Autodesk Fusion 360 part; units mm, degrees
(part 2 of 2)
extrude "PSU bottom support rail'" add sketch "草图1 (14)" along normal blind 6 separate body makes body 14 in component "04_PSU_Shelf_front"
ref_plane "工作平面2" through (0, 0, 14) normal (0, 0, 1) x (1, 0, 0) in component "04_PSU_Shelf_front"
sketch "草图2 (14)" plane through (0, 0, 14) normal (0, 0, 1) x (1, 0, 0) in component "04_PSU_Shelf_front"
  circle A0 centre (-13, 121) radius 1.7
extrude "M3x10 shelf to frame (1)" cut sketch "草图2 (14)" along normal blind 6 bodies 1 in component "01_Side_L_rear"
extrude "拉伸2'" cut sketch "草图2 (14)" along normal blind 6 bodies 14 in component "04_PSU_Shelf_front"
ref_plane "工作平面3" through (0, 0, 14) normal (0, 0, 1) x (1, 0, 0) in component "04_PSU_Shelf_front"
sketch "草图3 (14)" plane through (0, 0, 14) normal (0, 0, 1) x (1, 0, 0) in component "04_PSU_Shelf_front"
  circle A0 centre (257, 121) radius 1.7
extrude "M3x10 shelf to frame (1)'" cut sketch "草图3 (14)" along normal blind 6 bodies 3 in component "01_Side_R_rear"
extrude "拉伸3'" cut sketch "草图3 (14)" along normal blind 6 bodies 14 in component "04_PSU_Shelf_front"
ref_plane "工作平面4" through (0, 0, 14) normal (0, 0, 1) x (1, 0, 0) in component "04_PSU_Shelf_front"
sketch "草图4 (13)" plane through (0, 0, 14) normal (0, 0, 1) x (1, 0, 0) in component "04_PSU_Shelf_front"
  circle A0 centre (14, 117) radius 1.7
extrude "Hoop position adjustment end 1'" cut sketch "草图4 (13)" along normal blind 6 bodies 14 in component "04_PSU_Shelf_front"
ref_plane "工作平面5" through (0, 0, 14) normal (0, 0, 1) x (1, 0, 0) in component "04_PSU_Shelf_front"
sketch "草图5 (13)" plane through (0, 0, 14) normal (0, 0, 1) x (1, 0, 0) in component "04_PSU_Shelf_front"
  circle A0 centre (14, 125) radius 1.7
extrude "Hoop position adjustment end 2'" cut sketch "草图5 (13)" along normal blind 6 bodies 14 in component "04_PSU_Shelf_front"
ref_plane "工作平面6" through (0, 0, 14) normal (0, 0, 1) x (1, 0, 0) in component "04_PSU_Shelf_front"
sketch "草图6 (9)" plane through (0, 0, 14) normal (0, 0, 1) x (1, 0, 0) in component "04_PSU_Shelf_front"
  line L0 (12.3, 117) -> (15.7, 117)
  line L1 (15.7, 117) -> (15.7, 125)
  line L2 (15.7, 125) -> (12.3, 125)
  line L3 (12.3, 125) -> (12.3, 117)
extrude "Hoop position adjustment bridge'" cut sketch "草图6 (9)" along normal blind 6 bodies 14 in component "04_PSU_Shelf_front"
ref_plane "工作平面7" through (0, 0, 14) normal (0, 0, 1) x (1, 0, 0) in component "04_PSU_Shelf_front"
sketch "草图7 (9)" plane through (0, 0, 14) normal (0, 0, 1) x (1, 0, 0) in component "04_PSU_Shelf_front"
  circle A0 centre (166, 117) radius 1.7
extrude "Hoop position adjustment end 1 (1)'" cut sketch "草图7 (9)" along normal blind 6 bodies 14 in component "04_PSU_Shelf_front"
ref_plane "工作平面8" through (0, 0, 14) normal (0, 0, 1) x (1, 0, 0) in component "04_PSU_Shelf_front"
sketch "草图8 (9)" plane through (0, 0, 14) normal (0, 0, 1) x (1, 0, 0) in component "04_PSU_Shelf_front"
  circle A0 centre (166, 125) radius 1.7
extrude "Hoop position adjustment end 2 (1)'" cut sketch "草图8 (9)" along normal blind 6 bodies 14 in component "04_PSU_Shelf_front"
ref_plane "工作平面9" through (0, 0, 14) normal (0, 0, 1) x (1, 0, 0) in component "04_PSU_Shelf_front"
sketch "草图9 (9)" plane through (0, 0, 14) normal (0, 0, 1) x (1, 0, 0) in component "04_PSU_Shelf_front"
  line L0 (164.3, 117) -> (167.7, 117)
  line L1 (167.7, 117) -> (167.7, 125)
  line L2 (167.7, 125) -> (164.3, 125)
  line L3 (164.3, 125) -> (164.3, 117)
extrude "Hoop position adjustment bridge (1)'" cut sketch "草图9 (9)" along normal blind 6 bodies 14 in component "04_PSU_Shelf_front"
ref_plane "工作平面10" through (0, 0, 20) normal (0, 0, 1) x (1, 0, 0) in component "04_PSU_Shelf_front"
sketch "草图10 (7)" plane through (0, 0, 20) normal (0, 0, 1) x (1, 0, 0) in component "04_PSU_Shelf_front"
  line L0 (17.5, 106) -> (19.5, 106)
  line L1 (19.5, 106) -> (19.5, 136)
  line L2 (19.5, 136) -> (17.5, 136)
  line L3 (17.5, 136) -> (17.5, 106)
extrude "PSU fore aft locating stop'" add sketch "草图10 (7)" along normal blind 6 bodies 14 in component "04_PSU_Shelf_front"
ref_plane "工作平面11" through (0, 0, 20) normal (0, 0, 1) x (1, 0, 0) in component "04_PSU_Shelf_front"
sketch "草图11 (5)" plane through (0, 0, 20) normal (0, 0, 1) x (1, 0, 0) in component "04_PSU_Shelf_front"
  line L0 (160.5, 106) -> (162.5, 106)
  line L1 (162.5, 106) -> (162.5, 136)
  line L2 (162.5, 136) -> (160.5, 136)
  line L3 (160.5, 136) -> (160.5, 106)
extrude "PSU fore aft locating stop (1)'" add sketch "草图11 (5)" along normal blind 6 bodies 14 in component "04_PSU_Shelf_front"
ref_plane "工作平面12" through (0, 0, 20) normal (0, 0, 1) x (1, 0, 0) in component "04_PSU_Shelf_front"
sketch "草图12 (5)" plane through (0, 0, 20) normal (0, 0, 1) x (1, 0, 0) in component "04_PSU_Shelf_front"
  line L0 (19.5, 131.5) -> (160.5, 131.5)
  line L1 (160.5, 131.5) -> (160.5, 133.5)
  line L2 (160.5, 133.5) -> (19.5, 133.5)
  line L3 (19.5, 133.5) -> (19.5, 131.5)
extrude "PSU fan-side lower-edge lip" add sketch "草图12 (5)" along normal blind 6 bodies 14 in component "04_PSU_Shelf_front"
ref_plane "工作平面1" through (0, -117, 0) normal (0, 1, 0) x (0, 0, 1) in component "05_PSU_Hoop_front"
sketch "草图1 (15)" plane through (0, -117, 0) normal (0, 1, 0) x (1, 0, 0) in component "05_PSU_Hoop_front"
  line L0 (10, -20, 234) -> (18, -20, 234)
  line L1 (18, -20, 234) -> (18, -171, 234)
  line L2 (18, -171, 234) -> (162, -171, 234)
  line L3 (162, -171, 234) -> (162, -20, 234)
  line L4 (162, -20, 234) -> (170, -20, 234)
  line L5 (170, -20, 234) -> (170, -179, 234)
  line L6 (170, -179, 234) -> (10, -179, 234)
  line L7 (10, -179, 234) -> (10, -20, 234)
extrude "Removable PSU retaining hoop'" add sketch "草图1 (15)" along normal blind 8 separate body contours L0 L1 L2 L3 L4 L5 L6 L7 in plane through (0, 117, 0) normal (0, 1, 0) makes body 15 in component "05_PSU_Hoop_front"
ref_plane "工作平面2" through (0, 0, 20) normal (0, 0, 1) x (1, 0, 0) in component "05_PSU_Hoop_front"
sketch "草图2 (15)" plane through (0, 0, 20) normal (0, 0, 1) x (1, 0, 0) in component "05_PSU_Hoop_front"
  circle A0 centre (14, 121) radius 2.35
extrude "M3 long insert from underside'" cut sketch "草图2 (15)" along normal blind 8.2 bodies 15 in component "05_PSU_Hoop_front"
ref_plane "工作平面3" through (0, 0, 20) normal (0, 0, 1) x (1, 0, 0) in component "05_PSU_Hoop_front"
sketch "草图3 (15)" plane through (0, 0, 20) normal (0, 0, 1) x (1, 0, 0) in component "05_PSU_Hoop_front"
  circle A0 centre (166, 121) radius 2.35
extrude "M3 long insert from underside (1)'" cut sketch "草图3 (15)" along normal blind 8.2 bodies 15 in component "05_PSU_Hoop_front"
ref_plane "工作平面1" through (0, 0, 198) normal (0, 0, 1) x (1, 0, 0) in component "06_GPU_RearTower"
sketch "草图1 (16)" plane through (0, 0, 198) normal (0, 0, 1) x (1, 0, 0) in component "06_GPU_RearTower"
  line L0 (-38, 130) -> (-5, 130)
  line L1 (-5, 130) -> (-5, 226)
  line L2 (-5, 226) -> (-38, 226)
  line L3 (-38, 226) -> (-38, 130)
extrude "GPU tower foot" add sketch "草图1 (16)" along normal blind 6 separate body makes body 16 in component "06_GPU_RearTower"
ref_plane "工作平面2" through (0, 0, 204) normal (0, 0, 1) x (1, 0, 0) in component "06_GPU_RearTower"
sketch "草图2 (16)" plane through (0, 0, 204) normal (0, 0, 1) x (1, 0, 0) in component "06_GPU_RearTower"
  line L0 (-38, 130) -> (-30, 130)
  line L1 (-30, 130) -> (-30, 226)
  line L2 (-30, 226) -> (-38, 226)
  line L3 (-38, 226) -> (-38, 130)
extrude "GPU rear frame" add sketch "草图2 (16)" along normal blind 146 bodies 16 in component "06_GPU_RearTower"
ref_plane "工作平面3" through (-38, 0, 0) normal (1, 0, 0) x (0, 1, 0) in component "06_GPU_RearTower"
sketch "草图3 (16)" plane through (-38, 0, 0) normal (1, 0, 0) x (0, 0, -1) in component "06_GPU_RearTower"
  line L0 (-214, 144) -> (-212, 146)
  line L1 (-212, 146) -> (-212, 210)
  line L2 (-212, 210) -> (-214, 212)
  line L3 (-214, 212) -> (-308, 212)
  line L4 (-308, 212) -> (-310, 210)
  line L5 (-310, 210) -> (-310, 146)
  line L6 (-310, 146) -> (-308, 144)
  line L7 (-308, 144) -> (-214, 144)
extrude "Open display connector access" cut sketch "草图3 (16)" along normal blind 8 bodies 16 in component "06_GPU_RearTower"
ref_plane "工作平面4" through (0, 0, 198) normal (0, 0, 1) x (1, 0, 0) in component "06_GPU_RearTower"
sketch "草图4 (14)" plane through (0, 0, 198) normal (0, 0, 1) x (1, 0, 0) in component "06_GPU_RearTower"
  circle A0 centre (-13, 157.83) radius 1.7
extrude "M3x10 tower foot screw" cut sketch "草图4 (14)" along normal blind 6 bodies 16 in component "06_GPU_RearTower"
ref_plane "工作平面5" through (0, 0, 198) normal (0, 0, 1) x (1, 0, 0) in component "06_GPU_RearTower"
sketch "草图5 (14)" plane through (0, 0, 198) normal (0, 0, 1) x (1, 0, 0) in component "06_GPU_RearTower"
  circle A0 centre (-13, 169.83) radius 1.7
extrude "M3x10 tower foot screw (1)" cut sketch "草图5 (14)" along normal blind 6 bodies 16 in component "06_GPU_RearTower"
ref_plane "工作平面6" through (0, 0, 198) normal (0, 0, 1) x (1, 0, 0) in component "06_GPU_RearTower"
sketch "草图6 (10)" plane through (0, 0, 198) normal (0, 0, 1) x (1, 0, 0) in component "06_GPU_RearTower"
  circle A0 centre (-13, 163.83) radius 3.5
extrude "Access clearance above crossbeam screw head" cut sketch "草图6 (10)" along normal blind 3 bodies 16 in component "06_GPU_RearTower"
ref_plane "工作平面7" through (-38, 0, 0) normal (1, 0, 0) x (0, 1, 0) in component "06_GPU_RearTower"
sketch "草图7 (10)" plane through (-38, 0, 0) normal (1, 0, 0) x (0, 0, -1) in component "06_GPU_RearTower"
  circle A0 centre (-316, 136) radius 1.7
extrude "GPU bracket height slot end 1" cut sketch "草图7 (10)" along normal blind 8 bodies 16 in component "06_GPU_RearTower"
ref_plane "工作平面8" through (-38, 0, 0) normal (1, 0, 0) x (0, 1, 0) in component "06_GPU_RearTower"
sketch "草图8 (10)" plane through (-38, 0, 0) normal (1, 0, 0) x (0, 0, -1) in component "06_GPU_RearTower"
  circle A0 centre (-344, 136) radius 1.7
extrude "GPU bracket height slot end 2" cut sketch "草图8 (10)" along normal blind 8 bodies 16 in component "06_GPU_RearTower"
ref_plane "工作平面9" through (-38, 0, 0) normal (1, 0, 0) x (0, 1, 0) in component "06_GPU_RearTower"
sketch "草图9 (10)" plane through (-38, 0, 0) normal (1, 0, 0) x (0, 0, -1) in component "06_GPU_RearTower"
  line L0 (-316, 134.3) -> (-316, 137.7)
  line L1 (-316, 137.7) -> (-344, 137.7)
  line L2 (-344, 137.7) -> (-344, 134.3)
  line L3 (-344, 134.3) -> (-316, 134.3)
extrude "GPU bracket height slot bridge" cut sketch "草图9 (10)" along normal blind 8 bodies 16 in component "06_GPU_RearTower"
ref_plane "工作平面10" through (-38, 0, 0) normal (1, 0, 0) x (0, 1, 0) in component "06_GPU_RearTower"
sketch "草图10 (8)" plane through (-38, 0, 0) normal (1, 0, 0) x (0, 0, -1) in component "06_GPU_RearTower"
  circle A0 centre (-316, 220) radius 1.7
extrude "GPU bracket height slot end 1 (1)" cut sketch "草图10 (8)" along normal blind 8 bodies 16 in component "06_GPU_RearTower"
ref_plane "工作平面11" through (-38, 0, 0) normal (1, 0, 0) x (0, 1, 0) in component "06_GPU_RearTower"
sketch "草图11 (6)" plane through (-38, 0, 0) normal (1, 0, 0) x (0, 0, -1) in component "06_GPU_RearTower"
  circle A0 centre (-344, 220) radius 1.7
extrude "GPU bracket height slot end 2 (1)" cut sketch "草图11 (6)" along normal blind 8 bodies 16 in component "06_GPU_RearTower"
ref_plane "工作平面12" through (-38, 0, 0) normal (1, 0, 0) x (0, 1, 0) in component "06_GPU_RearTower"
sketch "草图12 (6)" plane through (-38, 0, 0) normal (1, 0, 0) x (0, 0, -1) in component "06_GPU_RearTower"
  line L0 (-316, 218.3) -> (-316, 221.7)
  line L1 (-316, 221.7) -> (-344, 221.7)
  line L2 (-344, 221.7) -> (-344, 218.3)
  line L3 (-344, 218.3) -> (-316, 218.3)
extrude "GPU bracket height slot bridge (1)" cut sketch "草图12 (6)" along normal blind 8 bodies 16 in component "06_GPU_RearTower"
ref_plane "工作平面1" through (0, 0, 316) normal (0, 0, 1) x (1, 0, 0) in component "07_GPU_RearSlider"
sketch "草图1 (17)" plane through (0, 0, 316) normal (0, 0, 1) x (1, 0, 0) in component "07_GPU_RearSlider"
  line L0 (-30, 130) -> (-20, 130)
  line L1 (-20, 130) -> (-20, 226)
  line L2 (-20, 226) -> (-30, 226)
  line L3 (-30, 226) -> (-30, 130)
extrude "GPU sliding carrier" add sketch "草图1 (17)" along normal blind 30 separate body makes body 17 in component "07_GPU_RearSlider"
ref_plane "工作平面2" through (0, 0, 330) normal (0, 0, 1) x (1, 0, 0) in component "07_GPU_RearSlider"
sketch "草图2 (17)" plane through (0, 0, 330) normal (0, 0, 1) x (1, 0, 0) in component "07_GPU_RearSlider"
  line L0 (-20, 130) -> (-1, 130)
  line L1 (-1, 130) -> (-1, 226)
  line L2 (-1, 226) -> (-20, 226)
  line L3 (-20, 226) -> (-20, 130)
extrude "GPU metal bracket screw ledge" add sketch "草图2 (17)" along normal blind 6 bodies 17 in component "07_GPU_RearSlider"
ref_plane "工作平面3" through (-30, 0, 0) normal (1, 0, 0) x (0, 1, 0) in component "07_GPU_RearSlider"
sketch "草图3 (17)" plane through (-30, 0, 0) normal (1, 0, 0) x (0, 0, -1) in component "07_GPU_RearSlider"
  circle A0 centre (-332, 136) radius 2.35
extrude "M3 long insert side pocket''''" cut sketch "草图3 (17)" along normal blind 8.2 bodies 17 in component "07_GPU_RearSlider"
ref_plane "工作平面4" through (-30, 0, 0) normal (1, 0, 0) x (0, 1, 0) in component "07_GPU_RearSlider"
sketch "草图4 (15)" plane through (-30, 0, 0) normal (1, 0, 0) x (0, 0, -1) in component "07_GPU_RearSlider"
  circle A0 centre (-332, 220) radius 2.35
extrude "M3 long insert side pocket (1)''''" cut sketch "草图4 (15)" along normal blind 8.2 bodies 17 in component "07_GPU_RearSlider"
ref_plane "工作平面5" through (0, 0, 330) normal (0, 0, 1) x (1, 0, 0) in component "07_GPU_RearSlider"
sketch "草图5 (15)" plane through (0, 0, 330) normal (0, 0, 1) x (1, 0, 0) in component "07_GPU_RearSlider"
  circle A0 centre (-7, 142) radius 1.7
extrude "GPU mounting screw Y adjustment end 1" cut sketch "草图5 (15)" along normal blind 6 bodies 17 in component "07_GPU_RearSlider"
ref_plane "工作平面6" through (0, 0, 330) normal (0, 0, 1) x (1, 0, 0) in component "07_GPU_RearSlider"
sketch "草图6 (11)" plane through (0, 0, 330) normal (0, 0, 1) x (1, 0, 0) in component "07_GPU_RearSlider"
  circle A0 centre (-7, 214) radius 1.7
extrude "GPU mounting screw Y adjustment end 2" cut sketch "草图6 (11)" along normal blind 6 bodies 17 in component "07_GPU_RearSlider"
ref_plane "工作平面7" through (0, 0, 330) normal (0, 0, 1) x (1, 0, 0) in component "07_GPU_RearSlider"
sketch "草图7 (11)" plane through (0, 0, 330) normal (0, 0, 1) x (1, 0, 0) in component "07_GPU_RearSlider"
  line L0 (-8.7, 142) -> (-5.3, 142)
  line L1 (-5.3, 142) -> (-5.3, 214)
  line L2 (-5.3, 214) -> (-8.7, 214)
  line L3 (-8.7, 214) -> (-8.7, 142)
extrude "GPU mounting screw Y adjustment bridge" cut sketch "草图7 (11)" along normal blind 6 bodies 17 in component "07_GPU_RearSlider"
ref_plane "工作平面8" through (0, 0, 316) normal (0, 0, 1) x (1, 0, 0) in component "07_GPU_RearSlider"
sketch "草图8 (11)" plane through (0, 0, 316) normal (0, 0, 1) x (1, 0, 0) in component "07_GPU_RearSlider"
  line L0 (-30, 145) -> (-20, 145)
  line L1 (-20, 145) -> (-20, 211)
  line L2 (-20, 211) -> (-30, 211)
  line L3 (-30, 211) -> (-30, 145)
extrude "Carrier display plug opening" cut sketch "草图8 (11)" along normal blind 13 bodies 17 in component "07_GPU_RearSlider"
ref_plane "工作平面1" through (0, 0, 324) normal (0, 0, 1) x (1, 0, 0) in component "08_GPU_SlidingNut"
sketch "草图1 (18)" plane through (0, 0, 324) normal (0, 0, 1) x (1, 0, 0) in component "08_GPU_SlidingNut"
  line L0 (-12, 165) -> (-2, 165)
  line L1 (-2, 165) -> (-2, 175)
  line L2 (-2, 175) -> (-12, 175)
  line L3 (-12, 175) -> (-12, 165)
extrude "M3 captive sliding insert block" add sketch "草图1 (18)" along normal blind 6 separate body makes body 18 in component "08_GPU_SlidingNut"
ref_plane "工作平面2" through (0, 0, 325.1) normal (0, 0, 1) x (1, 0, 0) in component "08_GPU_SlidingNut"
sketch "草图2 (18)" plane through (0, 0, 325.1) normal (0, 0, 1) x (1, 0, 0) in component "08_GPU_SlidingNut"
  circle A0 centre (-7, 170) radius 2.35
extrude "M3 heat insert pocket'''''''" cut sketch "草图2 (18)" along normal blind 4.7 bodies 18 in component "08_GPU_SlidingNut"
ref_plane "工作平面1" through (0, 0, 198) normal (0, 0, 1) x (1, 0, 0) in component "09_GPU_TailTower"
sketch "草图1 (19)" plane through (0, 0, 198) normal (0, 0, 1) x (1, 0, 0) in component "09_GPU_TailTower"
  line L0 (248, 153.83) -> (266, 153.83)
  line L1 (266, 153.83) -> (266, 212)
  line L2 (266, 212) -> (248, 212)
  line L3 (248, 212) -> (248, 153.83)
extrude "Tail support foot outside motherboard" add sketch "草图1 (19)" along normal blind 6 separate body makes body 19 in component "09_GPU_TailTower"
ref_plane "工作平面2" through (0, 0, 204) normal (0, 0, 1) x (1, 0, 0) in component "09_GPU_TailTower"
sketch "草图2 (19)" plane through (0, 0, 204) normal (0, 0, 1) x (1, 0, 0) in component "09_GPU_TailTower"
  line L0 (250, 176) -> (258, 176)
  line L1 (258, 176) -> (258, 212)
  line L2 (258, 212) -> (250, 212)
  line L3 (250, 212) -> (250, 176)
extrude "Tail support external upright" add sketch "草图2 (19)" along normal blind 46 bodies 19 in component "09_GPU_TailTower"
ref_plane "工作平面3" through (0, 0, 198) normal (0, 0, 1) x (1, 0, 0) in component "09_GPU_TailTower"
sketch "草图3 (18)" plane through (0, 0, 198) normal (0, 0, 1) x (1, 0, 0) in component "09_GPU_TailTower"
  circle A0 centre (257, 157.83) radius 1.7
extrude "M3x10 tail support foot screw" cut sketch "草图3 (18)" along normal blind 6 bodies 19 in component "09_GPU_TailTower"
ref_plane "工作平面4" through (0, 0, 198) normal (0, 0, 1) x (1, 0, 0) in component "09_GPU_TailTower"
sketch "草图4 (16)" plane through (0, 0, 198) normal (0, 0, 1) x (1, 0, 0) in component "09_GPU_TailTower"
  circle A0 centre (257, 169.83) radius 1.7
extrude "M3x10 tail support foot screw (1)" cut sketch "草图4 (16)" along normal blind 6 bodies 19 in component "09_GPU_TailTower"
ref_plane "工作平面5" through (0, 0, 198) normal (0, 0, 1) x (1, 0, 0) in component "09_GPU_TailTower"
sketch "草图5 (16)" plane through (0, 0, 198) normal (0, 0, 1) x (1, 0, 0) in component "09_GPU_TailTower"
  circle A0 centre (257, 163.83) radius 3.5
extrude "Crossbeam screw head clearance" cut sketch "草图5 (16)" along normal blind 3 bodies 19 in component "09_GPU_TailTower"
ref_plane "工作平面6" through (250, 0, 0) normal (1, 0, 0) x (0, 1, 0) in component "09_GPU_TailTower"
sketch "草图6 (12)" plane through (250, 0, 0) normal (1, 0, 0) x (0, 0, -1) in component "09_GPU_TailTower"
  circle A0 centre (-214, 184) radius 1.7
extrude "Tail pad height slot end 1" cut sketch "草图6 (12)" along normal blind 8 bodies 19 in component "09_GPU_TailTower"
ref_plane "工作平面7" through (250, 0, 0) normal (1, 0, 0) x (0, 1, 0) in component "09_GPU_TailTower"
sketch "草图7 (12)" plane through (250, 0, 0) normal (1, 0, 0) x (0, 0, -1) in component "09_GPU_TailTower"
  circle A0 centre (-238, 184) radius 1.7
extrude "Tail pad height slot end 2" cut sketch "草图7 (12)" along normal blind 8 bodies 19 in component "09_GPU_TailTower"
ref_plane "工作平面8" through (250, 0, 0) normal (1, 0, 0) x (0, 1, 0) in component "09_GPU_TailTower"
sketch "草图8 (12)" plane through (250, 0, 0) normal (1, 0, 0) x (0, 0, -1) in component "09_GPU_TailTower"
  line L0 (-214, 182.3) -> (-214, 185.7)
  line L1 (-214, 185.7) -> (-238, 185.7)
  line L2 (-238, 185.7) -> (-238, 182.3)
  line L3 (-238, 182.3) -> (-214, 182.3)
extrude "Tail pad height slot bridge" cut sketch "草图8 (12)" along normal blind 8 bodies 19 in component "09_GPU_TailTower"
ref_plane "工作平面9" through (250, 0, 0) normal (1, 0, 0) x (0, 1, 0) in component "09_GPU_TailTower"
sketch "草图9 (11)" plane through (250, 0, 0) normal (1, 0, 0) x (0, 0, -1) in component "09_GPU_TailTower"
  circle A0 centre (-214, 204) radius 1.7
extrude "Tail pad height slot end 1 (1)" cut sketch "草图9 (11)" along normal blind 8 bodies 19 in component "09_GPU_TailTower"
ref_plane "工作平面10" through (250, 0, 0) normal (1, 0, 0) x (0, 1, 0) in component "09_GPU_TailTower"
sketch "草图10 (9)" plane through (250, 0, 0) normal (1, 0, 0) x (0, 0, -1) in component "09_GPU_TailTower"
  circle A0 centre (-238, 204) radius 1.7
extrude "Tail pad height slot end 2 (1)" cut sketch "草图10 (9)" along normal blind 8 bodies 19 in component "09_GPU_TailTower"
ref_plane "工作平面11" through (250, 0, 0) normal (1, 0, 0) x (0, 1, 0) in component "09_GPU_TailTower"
sketch "草图11 (7)" plane through (250, 0, 0) normal (1, 0, 0) x (0, 0, -1) in component "09_GPU_TailTower"
  line L0 (-214, 202.3) -> (-214, 205.7)
  line L1 (-214, 205.7) -> (-238, 205.7)
  line L2 (-238, 205.7) -> (-238, 202.3)
  line L3 (-238, 202.3) -> (-214, 202.3)
extrude "Tail pad height slot bridge (1)" cut sketch "草图11 (7)" along normal blind 8 bodies 19 in component "09_GPU_TailTower"
ref_plane "工作平面1" through (0, 0, 212) normal (0, 0, 1) x (1, 0, 0) in component "10_GPU_TailSlider"
sketch "草图1 (20)" plane through (0, 0, 212) normal (0, 0, 1) x (1, 0, 0) in component "10_GPU_TailSlider"
  line L0 (240, 180) -> (250, 180)
  line L1 (250, 180) -> (250, 208)
  line L2 (250, 208) -> (240, 208)
  line L3 (240, 208) -> (240, 180)
extrude "Tail pad sliding upright" add sketch "草图1 (20)" along normal blind 28 separate body makes body 20 in component "10_GPU_TailSlider"
ref_plane "工作平面2" through (0, 0, 213) normal (0, 0, 1) x (1, 0, 0) in component "10_GPU_TailSlider"
sketch "草图2 (20)" plane through (0, 0, 213) normal (0, 0, 1) x (1, 0, 0) in component "10_GPU_TailSlider"
  line L0 (210, 180) -> (240, 180)
  line L1 (240, 180) -> (240, 208)
  line L2 (240, 208) -> (210, 208)
  line L3 (210, 208) -> (210, 180)
extrude "Tail support cantilever above motherboard" add sketch "草图2 (20)" along normal blind 6 bodies 20 in component "10_GPU_TailSlider"
ref_plane "工作平面3" through (241.8, 0, 0) normal (1, 0, 0) x (0, 1, 0) in component "10_GPU_TailSlider"
sketch "草图3 (19)" plane through (241.8, 0, 0) normal (1, 0, 0) x (0, 0, -1) in component "10_GPU_TailSlider"
  circle A0 centre (-226, 184) radius 2.35
extrude "M3 long insert side pocket'''''" cut sketch "草图3 (19)" along normal blind 8.2 bodies 20 in component "10_GPU_TailSlider"
ref_plane "工作平面4" through (241.8, 0, 0) normal (1, 0, 0) x (0, 1, 0) in component "10_GPU_TailSlider"
sketch "草图4 (17)" plane through (241.8, 0, 0) normal (1, 0, 0) x (0, 0, -1) in component "10_GPU_TailSlider"
  circle A0 centre (-226, 204) radius 2.35
extrude "M3 long insert side pocket (1)'''''" cut sketch "草图4 (17)" along normal blind 8.2 bodies 20 in component "10_GPU_TailSlider"
ref_plane "工作平面1" through (0, 0, 0) normal (0, 0, 1) x (1, 0, 0) in component "11_INSERT_FIT_FIRST"
sketch "草图1 (21)" plane through (0, 0, 0) normal (0, 0, 1) x (1, 0, 0) in component "11_INSERT_FIT_FIRST"
  line L0 (285, 0) -> (349, 0)
  line L1 (349, 0) -> (349, 30)
  line L2 (349, 30) -> (285, 30)
  line L3 (285, 30) -> (285, 0)
extrude "Insert fit coupon base" add sketch "草图1 (21)" along normal blind 3 separate body makes body 21 in component "11_INSERT_FIT_FIRST"
ref_plane "工作平面2" through (0, 0, 3) normal (0, 0, 1) x (1, 0, 0) in component "11_INSERT_FIT_FIRST"
sketch "草图2 (21)" plane through (0, 0, 3) normal (0, 0, 1) x (1, 0, 0) in component "11_INSERT_FIT_FIRST"
  circle A0 centre (297, 8) radius 4
extrude "short test boss 4.6" add sketch "草图2 (21)" along normal blind 10 bodies 21 in component "11_INSERT_FIT_FIRST"
ref_plane "工作平面3" through (0, 0, 8.1) normal (0, 0, 1) x (1, 0, 0) in component "11_INSERT_FIT_FIRST"
sketch "草图3 (20)" plane through (0, 0, 8.1) normal (0, 0, 1) x (1, 0, 0) in component "11_INSERT_FIT_FIRST"
  circle A0 centre (297, 8) radius 2.3
extrude "M3 heat insert pocket''''''''" cut sketch "草图3 (20)" along normal blind 4.7 bodies 21 in component "11_INSERT_FIT_FIRST"
ref_plane "工作平面4" through (0, 0, 3) normal (0, 0, 1) x (1, 0, 0) in component "11_INSERT_FIT_FIRST"
sketch "草图4 (18)" plane through (0, 0, 3) normal (0, 0, 1) x (1, 0, 0) in component "11_INSERT_FIT_FIRST"
  circle A0 centre (317, 8) radius 4
extrude "short test boss 4.7" add sketch "草图4 (18)" along normal blind 10 bodies 21 in component "11_INSERT_FIT_FIRST"
ref_plane "工作平面5" through (0, 0, 8.1) normal (0, 0, 1) x (1, 0, 0) in component "11_INSERT_FIT_FIRST"
sketch "草图5 (17)" plane through (0, 0, 8.1) normal (0, 0, 1) x (1, 0, 0) in component "11_INSERT_FIT_FIRST"
  circle A0 centre (317, 8) radius 2.35
extrude "M3 heat insert pocket (1)'''''''" cut sketch "草图5 (17)" along normal blind 4.7 bodies 21 in component "11_INSERT_FIT_FIRST"
ref_plane "工作平面6" through (0, 0, 3) normal (0, 0, 1) x (1, 0, 0) in component "11_INSERT_FIT_FIRST"
sketch "草图6 (13)" plane through (0, 0, 3) normal (0, 0, 1) x (1, 0, 0) in component "11_INSERT_FIT_FIRST"
  circle A0 centre (337, 8) radius 4
extrude "short test boss 4.8" add sketch "草图6 (13)" along normal blind 10 bodies 21 in component "11_INSERT_FIT_FIRST"
ref_plane "工作平面7" through (0, 0, 8.1) normal (0, 0, 1) x (1, 0, 0) in component "11_INSERT_FIT_FIRST"
sketch "草图7 (13)" plane through (0, 0, 8.1) normal (0, 0, 1) x (1, 0, 0) in component "11_INSERT_FIT_FIRST"
  circle A0 centre (337, 8) radius 2.4
extrude "M3 heat insert pocket (2)'''''" cut sketch "草图7 (13)" along normal blind 4.7 bodies 21 in component "11_INSERT_FIT_FIRST"
ref_plane "工作平面8" through (0, 0, 3) normal (0, 0, 1) x (1, 0, 0) in component "11_INSERT_FIT_FIRST"
sketch "草图8 (13)" plane through (0, 0, 3) normal (0, 0, 1) x (1, 0, 0) in component "11_INSERT_FIT_FIRST"
  circle A0 centre (297, 22) radius 4
extrude "long test boss 4.6" add sketch "草图8 (13)" along normal blind 13 bodies 21 in component "11_INSERT_FIT_FIRST"
ref_plane "工作平面9" through (0, 0, 7.6) normal (0, 0, 1) x (1, 0, 0) in component "11_INSERT_FIT_FIRST"
sketch "草图9 (12)" plane through (0, 0, 7.6) normal (0, 0, 1) x (1, 0, 0) in component "11_INSERT_FIT_FIRST"
  circle A0 centre (297, 22) radius 2.3
extrude "M3 heat insert pocket (3)'" cut sketch "草图9 (12)" along normal blind 8.2 bodies 21 in component "11_INSERT_FIT_FIRST"
ref_plane "工作平面10" through (0, 0, 3) normal (0, 0, 1) x (1, 0, 0) in component "11_INSERT_FIT_FIRST"
sketch "草图10 (10)" plane through (0, 0, 3) normal (0, 0, 1) x (1, 0, 0) in component "11_INSERT_FIT_FIRST"
  circle A0 centre (317, 22) radius 4
extrude "long test boss 4.7" add sketch "草图10 (10)" along normal blind 13 bodies 21 in component "11_INSERT_FIT_FIRST"
ref_plane "工作平面11" through (0, 0, 7.6) normal (0, 0, 1) x (1, 0, 0) in component "11_INSERT_FIT_FIRST"
sketch "草图11 (8)" plane through (0, 0, 7.6) normal (0, 0, 1) x (1, 0, 0) in component "11_INSERT_FIT_FIRST"
  circle A0 centre (317, 22) radius 2.35
extrude "M3 heat insert pocket (4)'" cut sketch "草图11 (8)" along normal blind 8.2 bodies 21 in component "11_INSERT_FIT_FIRST"
ref_plane "工作平面12" through (0, 0, 3) normal (0, 0, 1) x (1, 0, 0) in component "11_INSERT_FIT_FIRST"
sketch "草图12 (7)" plane through (0, 0, 3) normal (0, 0, 1) x (1, 0, 0) in component "11_INSERT_FIT_FIRST"
  circle A0 centre (337, 22) radius 4
extrude "long test boss 4.8" add sketch "草图12 (7)" along normal blind 13 bodies 21 in component "11_INSERT_FIT_FIRST"
ref_plane "工作平面13" through (0, 0, 7.6) normal (0, 0, 1) x (1, 0, 0) in component "11_INSERT_FIT_FIRST"
sketch "草图13 (4)" plane through (0, 0, 7.6) normal (0, 0, 1) x (1, 0, 0) in component "11_INSERT_FIT_FIRST"
  circle A0 centre (337, 22) radius 2.4
extrude "M3 heat insert pocket (5)'" cut sketch "草图13 (4)" along normal blind 8.2 bodies 21 in component "11_INSERT_FIT_FIRST"
ref_plane "工作平面1" through (0, 0, 208) normal (0, 0, 1) x (1, 0, 0) in component "REF_MSI_Z390_A_PRO_304.8x243.84"
sketch "草图1 (22)" plane through (0, 0, 208) normal (0, 0, 1) x (1, 0, 0) in component "REF_MSI_Z390_A_PRO_304.8x243.84"
  line L0 (0, 0) -> (243.84, 0)
  line L1 (243.84, 0) -> (243.84, 304.8)
  line L2 (243.84, 304.8) -> (0, 304.8)
  line L3 (0, 304.8) -> (0, 0)
extrude "Motherboard envelope ONLY" add sketch "草图1 (22)" along normal blind 1.6 separate body makes body 22 in component "REF_MSI_Z390_A_PRO_304.8x243.84"
ref_plane "工作平面2" through (0, 0, 208) normal (0, 0, 1) x (1, 0, 0) in component "REF_MSI_Z390_A_PRO_304.8x243.84"
sketch "草图2 (22)" plane through (0, 0, 208) normal (0, 0, 1) x (1, 0, 0) in component "REF_MSI_Z390_A_PRO_304.8x243.84"
  circle A0 centre (10.16, 288.29) radius 1.98
extrude "ATX A" cut sketch "草图2 (22)" along normal blind 1.6 bodies 22 in component "REF_MSI_Z390_A_PRO_304.8x243.84"
ref_plane "工作平面3" through (0, 0, 208) normal (0, 0, 1) x (1, 0, 0) in component "REF_MSI_Z390_A_PRO_304.8x243.84"
sketch "草图3 (21)" plane through (0, 0, 208) normal (0, 0, 1) x (1, 0, 0) in component "REF_MSI_Z390_A_PRO_304.8x243.84"
  circle A0 centre (10.16, 163.83) radius 1.98
extrude "ATX C" cut sketch "草图3 (21)" along normal blind 1.6 bodies 22 in component "REF_MSI_Z390_A_PRO_304.8x243.84"
ref_plane "工作平面4" through (0, 0, 208) normal (0, 0, 1) x (1, 0, 0) in component "REF_MSI_Z390_A_PRO_304.8x243.84"
sketch "草图4 (19)" plane through (0, 0, 208) normal (0, 0, 1) x (1, 0, 0) in component "REF_MSI_Z390_A_PRO_304.8x243.84"
  circle A0 centre (33.02, 6.35) radius 1.98
extrude "ATX F" cut sketch "草图4 (19)" along normal blind 1.6 bodies 22 in component "REF_MSI_Z390_A_PRO_304.8x243.84"
ref_plane "工作平面5" through (0, 0, 208) normal (0, 0, 1) x (1, 0, 0) in component "REF_MSI_Z390_A_PRO_304.8x243.84"
sketch "草图5 (18)" plane through (0, 0, 208) normal (0, 0, 1) x (1, 0, 0) in component "REF_MSI_Z390_A_PRO_304.8x243.84"
  circle A0 centre (165.1, 288.29) radius 1.98
extrude "ATX G" cut sketch "草图5 (18)" along normal blind 1.6 bodies 22 in component "REF_MSI_Z390_A_PRO_304.8x243.84"
ref_plane "工作平面6" through (0, 0, 208) normal (0, 0, 1) x (1, 0, 0) in component "REF_MSI_Z390_A_PRO_304.8x243.84"
sketch "草图6 (14)" plane through (0, 0, 208) normal (0, 0, 1) x (1, 0, 0) in component "REF_MSI_Z390_A_PRO_304.8x243.84"
  circle A0 centre (165.1, 163.83) radius 1.98
extrude "ATX H" cut sketch "草图6 (14)" along normal blind 1.6 bodies 22 in component "REF_MSI_Z390_A_PRO_304.8x243.84"
ref_plane "工作平面7" through (0, 0, 208) normal (0, 0, 1) x (1, 0, 0) in component "REF_MSI_Z390_A_PRO_304.8x243.84"
sketch "草图7 (14)" plane through (0, 0, 208) normal (0, 0, 1) x (1, 0, 0) in component "REF_MSI_Z390_A_PRO_304.8x243.84"
  circle A0 centre (165.1, 6.35) radius 1.98
extrude "ATX J" cut sketch "草图7 (14)" along normal blind 1.6 bodies 22 in component "REF_MSI_Z390_A_PRO_304.8x243.84"
ref_plane "工作平面8" through (0, 0, 208) normal (0, 0, 1) x (1, 0, 0) in component "REF_MSI_Z390_A_PRO_304.8x243.84"
sketch "草图8 (14)" plane through (0, 0, 208) normal (0, 0, 1) x (1, 0, 0) in component "REF_MSI_Z390_A_PRO_304.8x243.84"
  circle A0 centre (237.49, 288.29) radius 1.98
extrude "ATX K" cut sketch "草图8 (14)" along normal blind 1.6 bodies 22 in component "REF_MSI_Z390_A_PRO_304.8x243.84"
ref_plane "工作平面9" through (0, 0, 208) normal (0, 0, 1) x (1, 0, 0) in component "REF_MSI_Z390_A_PRO_304.8x243.84"
sketch "草图9 (13)" plane through (0, 0, 208) normal (0, 0, 1) x (1, 0, 0) in component "REF_MSI_Z390_A_PRO_304.8x243.84"
  circle A0 centre (237.49, 163.83) radius 1.98
extrude "ATX L" cut sketch "草图9 (13)" along normal blind 1.6 bodies 22 in component "REF_MSI_Z390_A_PRO_304.8x243.84"
ref_plane "工作平面10" through (0, 0, 208) normal (0, 0, 1) x (1, 0, 0) in component "REF_MSI_Z390_A_PRO_304.8x243.84"
sketch "草图10 (11)" plane through (0, 0, 208) normal (0, 0, 1) x (1, 0, 0) in component "REF_MSI_Z390_A_PRO_304.8x243.84"
  circle A0 centre (237.49, 6.35) radius 1.98
extrude "ATX M" cut sketch "草图10 (11)" along normal blind 1.6 bodies 22 in component "REF_MSI_Z390_A_PRO_304.8x243.84"
ref_plane "工作平面1" through (0, 0, 20) normal (0, 0, 1) x (1, 0, 0) in component "REF_ENERMAX_ERV650G_AHG_140x86x150_FAN_PLUS_Y"
sketch "草图1 (23)" plane through (0, 0, 20) normal (0, 0, 1) x (1, 0, 0) in component "REF_ENERMAX_ERV650G_AHG_140x86x150_FAN_PLUS_Y"
  line L0 (20, 45) -> (160, 45)
  line L1 (160, 45) -> (160, 131)
  line L2 (160, 131) -> (20, 131)
  line L3 (20, 131) -> (20, 45)
extrude "PSU envelope ONLY" add sketch "草图1 (23)" along normal blind 150 separate body makes body 23 in component "REF_ENERMAX_ERV650G_AHG_140x86x150_FAN_PLUS_Y"
ref_plane "工作平面1" through (0, 0, 219) normal (0, 0, 1) x (1, 0, 0) in component "REF_GPU_BODY_223x40x114_APPROX_SLOT"
sketch "草图1 (24)" plane through (0, 0, 219) normal (0, 0, 1) x (1, 0, 0) in component "REF_GPU_BODY_223x40x114_APPROX_SLOT"
  line L0 (0, 155) -> (223, 155)
  line L1 (223, 155) -> (223, 195)
  line L2 (223, 195) -> (0, 195)
  line L3 (0, 195) -> (0, 155)
extrude "GPU body envelope ONLY - slot offset approximate" add sketch "草图1 (24)" along normal blind 114 separate body makes body 24 in component "REF_GPU_BODY_223x40x114_APPROX_SLOT"
ref_plane "工作平面1" through (0, -131, 0) normal (0, 1, 0) x (0, 0, 1) in component "REF_PSU_FAN_FACE_PLUS_Y"
sketch "草图1 (25)" plane through (0, -131, 0) normal (0, 1, 0) x (1, 0, 0) in component "REF_PSU_FAN_FACE_PLUS_Y"
  circle A0 through (150, -95, 262) (60, -43.0385, 262) (60, -146.9615, 262)
extrude "PSU intake direction marker ONLY" add sketch "草图1 (25)" along normal blind 0.3 separate body contours A0 in plane through (0, 131, 0) normal (0, 1, 0) makes body 25 in component "REF_PSU_FAN_FACE_PLUS_Y"
ref_plane "工作平面11" through (0, 0, 14) normal (0, 0, 1) x (1, 0, 0) in component "01_Side_L_rear"
sketch "草图11 (9)" plane through (0, 0, 14) normal (0, 0, 1) x (1, 0, 0) in component "01_Side_L_rear"
  line L0 (-22, 40) -> (-4, 40)
  line L1 (-4, 40) -> (-4, 70)
  line L2 (-4, 70) -> (-22, 70)
  line L3 (-22, 70) -> (-22, 40)
extrude "PSU seat corrected rear 55" cut sketch "草图11 (9)" along normal blind 6 bodies 1 in component "01_Side_L_rear"
ref_plane "工作平面12" through (0, 0, 14) normal (0, 0, 1) x (1, 0, 0) in component "01_Side_L_rear"
sketch "草图12 (8)" plane through (0, 0, 14) normal (0, 0, 1) x (1, 0, 0) in component "01_Side_L_rear"
  line L0 (-22, 106) -> (-4, 106)
  line L1 (-4, 106) -> (-4, 136)
  line L2 (-4, 136) -> (-22, 136)
  line L3 (-22, 136) -> (-22, 106)
extrude "PSU seat final 121" cut sketch "草图12 (8)" along normal blind 6 bodies 1 in component "01_Side_L_rear"
ref_plane "工作平面11" through (0, 0, 14) normal (0, 0, 1) x (1, 0, 0) in component "01_Side_R_rear"
sketch "草图11 (10)" plane through (0, 0, 14) normal (0, 0, 1) x (1, 0, 0) in component "01_Side_R_rear"
  line L0 (248, 40) -> (266, 40)
  line L1 (266, 40) -> (266, 70)
  line L2 (266, 70) -> (248, 70)
  line L3 (248, 70) -> (248, 40)
extrude "PSU seat final 55" cut sketch "草图11 (10)" along normal blind 6 bodies 3 in component "01_Side_R_rear"
ref_plane "工作平面12" through (0, 0, 14) normal (0, 0, 1) x (1, 0, 0) in component "01_Side_R_rear"
sketch "草图12 (9)" plane through (0, 0, 14) normal (0, 0, 1) x (1, 0, 0) in component "01_Side_R_rear"
  line L0 (248, 106) -> (266, 106)
  line L1 (266, 106) -> (266, 136)
  line L2 (266, 136) -> (248, 136)
  line L3 (248, 136) -> (248, 106)
extrude "PSU seat final 121'" cut sketch "草图12 (9)" along normal blind 6 bodies 3 in component "01_Side_R_rear"
ref_plane "工作平面15" through (0, 0, 203.3) normal (0, 0, 1) x (1, 0, 0) in component "03_BoardBeam_PCI"
sketch "草图15 (2)" plane through (0, 0, 203.3) normal (0, 0, 1) x (1, 0, 0) in component "03_BoardBeam_PCI"
  circle A0 centre (10.16, 288.29) radius 2.35
extrude "Open board insert top" cut sketch "草图15 (2)" along normal blind 4.7 bodies 11 in component "03_BoardBeam_PCI"
ref_plane "工作平面19" through (0, 0, 203.3) normal (0, 0, 1) x (1, 0, 0) in component "03_BoardBeam_MID"
sketch "草图19" plane through (0, 0, 203.3) normal (0, 0, 1) x (1, 0, 0) in component "03_BoardBeam_MID"
  circle A0 centre (10.16, 163.83) radius 2.35
extrude "Open board insert top'" cut sketch "草图19" along normal blind 4.7 bodies 10 in component "03_BoardBeam_MID"
ref_plane "工作平面15" through (0, 0, 203.3) normal (0, 0, 1) x (1, 0, 0) in component "03_BoardBeam_CPU"
sketch "草图15 (3)" plane through (0, 0, 203.3) normal (0, 0, 1) x (1, 0, 0) in component "03_BoardBeam_CPU"
  circle A0 centre (33.02, 6.35) radius 2.35
extrude "Open board insert top''" cut sketch "草图15 (3)" along normal blind 4.7 bodies 9 in component "03_BoardBeam_CPU"
ref_plane "工作平面16" through (0, 0, 203.3) normal (0, 0, 1) x (1, 0, 0) in component "03_BoardBeam_PCI"
sketch "草图16 (2)" plane through (0, 0, 203.3) normal (0, 0, 1) x (1, 0, 0) in component "03_BoardBeam_PCI"
  circle A0 centre (165.1, 288.29) radius 2.35
extrude "Open board insert top (1)" cut sketch "草图16 (2)" along normal blind 4.7 bodies 11 in component "03_BoardBeam_PCI"
ref_plane "工作平面20" through (0, 0, 203.3) normal (0, 0, 1) x (1, 0, 0) in component "03_BoardBeam_MID"
sketch "草图20" plane through (0, 0, 203.3) normal (0, 0, 1) x (1, 0, 0) in component "03_BoardBeam_MID"
  circle A0 centre (165.1, 163.83) radius 2.35
extrude "Open board insert top (1)'" cut sketch "草图20" along normal blind 4.7 bodies 10 in component "03_BoardBeam_MID"
ref_plane "工作平面16" through (0, 0, 203.3) normal (0, 0, 1) x (1, 0, 0) in component "03_BoardBeam_CPU"
sketch "草图16 (3)" plane through (0, 0, 203.3) normal (0, 0, 1) x (1, 0, 0) in component "03_BoardBeam_CPU"
  circle A0 centre (165.1, 6.35) radius 2.35
extrude "Open board insert top (1)''" cut sketch "草图16 (3)" along normal blind 4.7 bodies 9 in component "03_BoardBeam_CPU"
ref_plane "工作平面17" through (0, 0, 203.3) normal (0, 0, 1) x (1, 0, 0) in component "03_BoardBeam_PCI"
sketch "草图17 (2)" plane through (0, 0, 203.3) normal (0, 0, 1) x (1, 0, 0) in component "03_BoardBeam_PCI"
  circle A0 centre (237.49, 288.29) radius 2.35
extrude "Open board insert top (2)" cut sketch "草图17 (2)" along normal blind 4.7 bodies 11 in component "03_BoardBeam_PCI"
ref_plane "工作平面21" through (0, 0, 203.3) normal (0, 0, 1) x (1, 0, 0) in component "03_BoardBeam_MID"
sketch "草图21" plane through (0, 0, 203.3) normal (0, 0, 1) x (1, 0, 0) in component "03_BoardBeam_MID"
  circle A0 centre (237.49, 163.83) radius 2.35
extrude "Open board insert top (2)'" cut sketch "草图21" along normal blind 4.7 bodies 10 in component "03_BoardBeam_MID"
ref_plane "工作平面17" through (0, 0, 203.3) normal (0, 0, 1) x (1, 0, 0) in component "03_BoardBeam_CPU"
sketch "草图17 (3)" plane through (0, 0, 203.3) normal (0, 0, 1) x (1, 0, 0) in component "03_BoardBeam_CPU"
  circle A0 centre (237.49, 6.35) radius 2.35
extrude "Open board insert top (2)''" cut sketch "草图17 (3)" along normal blind 4.7 bodies 9 in component "03_BoardBeam_CPU"
ref_plane "工作平面3" through (0, 0, 325.3) normal (0, 0, 1) x (1, 0, 0) in component "08_GPU_SlidingNut"
sketch "草图3 (22)" plane through (0, 0, 325.3) normal (0, 0, 1) x (1, 0, 0) in component "08_GPU_SlidingNut"
  circle A0 centre (-7, 170) radius 2.35
extrude "Open nut top" cut sketch "草图3 (22)" along normal blind 4.7 bodies 18 in component "08_GPU_SlidingNut"
ref_plane "工作平面14" through (0, 0, 8.3) normal (0, 0, 1) x (1, 0, 0) in component "11_INSERT_FIT_FIRST"
sketch "草图14 (4)" plane through (0, 0, 8.3) normal (0, 0, 1) x (1, 0, 0) in component "11_INSERT_FIT_FIRST"
  circle A0 centre (297, 8) radius 2.3
extrude "Open coupon top" cut sketch "草图14 (4)" along normal blind 4.7 bodies 21 in component "11_INSERT_FIT_FIRST"
ref_plane "工作平面15" through (0, 0, 8.3) normal (0, 0, 1) x (1, 0, 0) in component "11_INSERT_FIT_FIRST"
sketch "草图15 (4)" plane through (0, 0, 8.3) normal (0, 0, 1) x (1, 0, 0) in component "11_INSERT_FIT_FIRST"
  circle A0 centre (317, 8) radius 2.35
extrude "Open coupon top (1)" cut sketch "草图15 (4)" along normal blind 4.7 bodies 21 in component "11_INSERT_FIT_FIRST"
ref_plane "工作平面16" through (0, 0, 8.3) normal (0, 0, 1) x (1, 0, 0) in component "11_INSERT_FIT_FIRST"
sketch "草图16 (4)" plane through (0, 0, 8.3) normal (0, 0, 1) x (1, 0, 0) in component "11_INSERT_FIT_FIRST"
  circle A0 centre (337, 8) radius 2.4
extrude "Open coupon top (2)" cut sketch "草图16 (4)" along normal blind 4.7 bodies 21 in component "11_INSERT_FIT_FIRST"
ref_plane "工作平面17" through (0, 0, 7.8) normal (0, 0, 1) x (1, 0, 0) in component "11_INSERT_FIT_FIRST"
sketch "草图17 (4)" plane through (0, 0, 7.8) normal (0, 0, 1) x (1, 0, 0) in component "11_INSERT_FIT_FIRST"
  circle A0 centre (297, 22) radius 2.3
extrude "Open coupon top (3)" cut sketch "草图17 (4)" along normal blind 8.2 bodies 21 in component "11_INSERT_FIT_FIRST"
ref_plane "工作平面18" through (0, 0, 7.8) normal (0, 0, 1) x (1, 0, 0) in component "11_INSERT_FIT_FIRST"
sketch "草图18 (2)" plane through (0, 0, 7.8) normal (0, 0, 1) x (1, 0, 0) in component "11_INSERT_FIT_FIRST"
  circle A0 centre (317, 22) radius 2.35
extrude "Open coupon top (4)" cut sketch "草图18 (2)" along normal blind 8.2 bodies 21 in component "11_INSERT_FIT_FIRST"
ref_plane "工作平面19" through (0, 0, 7.8) normal (0, 0, 1) x (1, 0, 0) in component "11_INSERT_FIT_FIRST"
sketch "草图19 (2)" plane through (0, 0, 7.8) normal (0, 0, 1) x (1, 0, 0) in component "11_INSERT_FIT_FIRST"
  circle A0 centre (337, 22) radius 2.4
extrude "Open coupon top (5)" cut sketch "草图19 (2)" along normal blind 8.2 bodies 21 in component "11_INSERT_FIT_FIRST"
ref_plane "工作平面13" through (0, 0, 20) normal (0, 0, 1) x (1, 0, 0) in component "04_PSU_Shelf_rear"
sketch "草图13 (5)" plane through (0, 0, 20) normal (0, 0, 1) x (1, 0, 0) in component "04_PSU_Shelf_rear"
  line L0 (17.5, 46.8) -> (19.5, 46.8)
  line L1 (19.5, 46.8) -> (19.5, 63.2)
  line L2 (19.5, 63.2) -> (17.5, 63.2)
  line L3 (17.5, 63.2) -> (17.5, 46.8)
extrude "Hoop travel clearance in locating stop" cut sketch "草图13 (5)" along normal blind 6 bodies 12 in component "04_PSU_Shelf_rear"
ref_plane "工作平面14" through (0, 0, 20) normal (0, 0, 1) x (1, 0, 0) in component "04_PSU_Shelf_rear"
sketch "草图14 (5)" plane through (0, 0, 20) normal (0, 0, 1) x (1, 0, 0) in component "04_PSU_Shelf_rear"
  line L0 (160.5, 46.8) -> (162.5, 46.8)
  line L1 (162.5, 46.8) -> (162.5, 63.2)
  line L2 (162.5, 63.2) -> (160.5, 63.2)
  line L3 (160.5, 63.2) -> (160.5, 46.8)
extrude "Hoop travel clearance in locating stop (1)" cut sketch "草图14 (5)" along normal blind 6 bodies 12 in component "04_PSU_Shelf_rear"
ref_plane "工作平面13" through (0, 0, 20) normal (0, 0, 1) x (1, 0, 0) in component "04_PSU_Shelf_front"
sketch "草图13 (6)" plane through (0, 0, 20) normal (0, 0, 1) x (1, 0, 0) in component "04_PSU_Shelf_front"
  line L0 (17.5, 112.8) -> (19.5, 112.8)
  line L1 (19.5, 112.8) -> (19.5, 129.2)
  line L2 (19.5, 129.2) -> (17.5, 129.2)
  line L3 (17.5, 129.2) -> (17.5, 112.8)
extrude "Hoop travel clearance in locating stop'" cut sketch "草图13 (6)" along normal blind 6 bodies 14 in component "04_PSU_Shelf_front"
ref_plane "工作平面14" through (0, 0, 20) normal (0, 0, 1) x (1, 0, 0) in component "04_PSU_Shelf_front"
sketch "草图14 (6)" plane through (0, 0, 20) normal (0, 0, 1) x (1, 0, 0) in component "04_PSU_Shelf_front"
  line L0 (160.5, 112.8) -> (162.5, 112.8)
  line L1 (162.5, 112.8) -> (162.5, 129.2)
  line L2 (162.5, 129.2) -> (160.5, 129.2)
  line L3 (160.5, 129.2) -> (160.5, 112.8)
extrude "Hoop travel clearance in locating stop (1)'" cut sketch "草图14 (6)" along normal blind 6 bodies 14 in component "04_PSU_Shelf_front"
component "01_Side_L_rear" placed x (1, 0, 0) y (0, 1, 0) z (0, 0, 1) at (0, 0, 0)
component "01_Side_L_front" placed x (1, 0, 0) y (0, 1, 0) z (0, 0, 1) at (0, 0, 0)
component "01_Side_R_rear" placed x (1, 0, 0) y (0, 1, 0) z (0, 0, 1) at (0, 0, 0)
component "01_Side_R_front" placed x (1, 0, 0) y (0, 1, 0) z (0, 0, 1) at (0, 0, 0)
component "02_Splice_L_low" placed x (1, 0, 0) y (0, 1, 0) z (0, 0, 1) at (0, 0, 0)
component "02_Splice_L_high" placed x (1, 0, 0) y (0, 1, 0) z (0, 0, 1) at (0, 0, 0)
component "02_Splice_R_low" placed x (1, 0, 0) y (0, 1, 0) z (0, 0, 1) at (0, 0, 0)
component "02_Splice_R_high" placed x (1, 0, 0) y (0, 1, 0) z (0, 0, 1) at (0, 0, 0)
component "03_BoardBeam_CPU" placed x (1, 0, 0) y (0, 1, 0) z (0, 0, 1) at (0, 0, 0)
component "03_BoardBeam_MID" placed x (1, 0, 0) y (0, 1, 0) z (0, 0, 1) at (0, 0, 0)
component "03_BoardBeam_PCI" placed x (1, 0, 0) y (0, 1, 0) z (0, 0, 1) at (0, 0, 0)
component "04_PSU_Shelf_rear" placed x (1, 0, 0) y (0, 1, 0) z (0, 0, 1) at (0, 0, 0)
component "05_PSU_Hoop_rear" placed x (1, 0, 0) y (0, 1, 0) z (0, 0, 1) at (0, 0, 0)
component "04_PSU_Shelf_front" placed x (1, 0, 0) y (0, 1, 0) z (0, 0, 1) at (0, 0, 0)
component "05_PSU_Hoop_front" placed x (1, 0, 0) y (0, 1, 0) z (0, 0, 1) at (0, 0, 0)
component "06_GPU_RearTower" placed x (1, 0, 0) y (0, 1, 0) z (0, 0, 1) at (0, 0, 0)
component "07_GPU_RearSlider" placed x (1, 0, 0) y (0, 1, 0) z (0, 0, 1) at (0, 0, 0)
component "08_GPU_SlidingNut" placed x (1, 0, 0) y (0, 1, 0) z (0, 0, 1) at (0, 0, 0)
component "09_GPU_TailTower" placed x (1, 0, 0) y (0, 1, 0) z (0, 0, 1) at (0, 0, 0)
component "10_GPU_TailSlider" placed x (1, 0, 0) y (0, 1, 0) z (0, 0, 1) at (0, 0, 0)
component "11_INSERT_FIT_FIRST" placed x (1, 0, 0) y (0, 1, 0) z (0, 0, 1) at (0, 0, 0)
component "REF_MSI_Z390_A_PRO_304.8x243.84" placed x (1, 0, 0) y (0, 1, 0) z (0, 0, 1) at (0, 0, 0)
component "REF_ENERMAX_ERV650G_AHG_140x86x150_FAN_PLUS_Y" placed x (1, 0, 0) y (0, 1, 0) z (0, 0, 1) at (0, 0, 0)
component "REF_GPU_BODY_223x40x114_APPROX_SLOT" placed x (1, 0, 0) y (0, 1, 0) z (0, 0, 1) at (0, 0, 0)
component "REF_PSU_FAN_FACE_PLUS_Y" placed x (1, 0, 0) y (0, 1, 0) z (0, 0, 1) at (0, 0, 0)
equation "frame_height = 190 mm" comment "Regeneration configuration; fixed sketch positions also require script regeneration"
equation "insert_bore = 4.7 mm" comment "Regeneration configuration; fixed sketch positions also require script regeneration"
equation "short_pocket = 4.7 mm" comment "Regeneration configuration; fixed sketch positions also require script regeneration"
equation "long_pocket = 8.2 mm" comment "Regeneration configuration; fixed sketch positions also require script regeneration"
equation "board_gap = 10 mm" comment "Regeneration configuration; fixed sketch positions also require script regeneration"
equation "frame_width = 288 mm" comment "Regeneration configuration; fixed sketch positions also require script regeneration"
equation "psu_x = 20 mm" comment "Regeneration configuration; fixed sketch positions also require script regeneration"
equation "psu_y = 45 mm" comment "Regeneration configuration; fixed sketch positions also require script regeneration"
equation "psu_z = 20 mm" comment "Regeneration configuration; fixed sketch positions also require script regeneration"
equation "gpu_slot_y = 155 mm" comment "Regeneration configuration; fixed sketch positions also require script regeneration"
